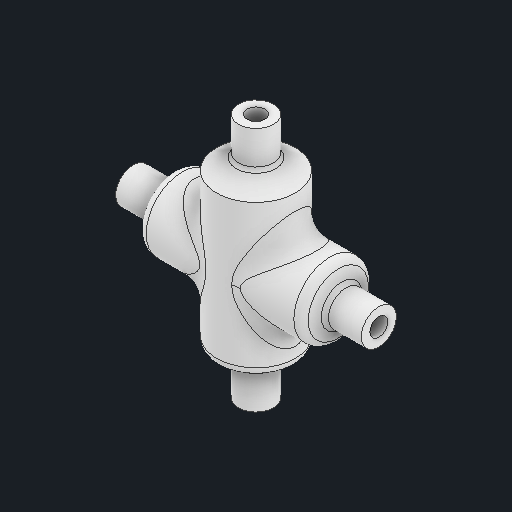
# Autodesk Inventor part: C
Saved by Autodesk Inventor 2026.2 (Build 302298010, 298A)
## iProperties
Created: 2026-03-19
Part Number: C
Material: PC/ABS 플라스틱
Document SubType Name: Modeling
Designer: work
Density: 1.1 g/cm^3
Appearance: 매끄러움 - 흰색
Mass: 15.833 g
Surface Area: 45.1342 cm^2
Volume: 14.3936 cm^3
Author: work
Autodesk Inventor part; units mm, degrees
ref_plane "YZ Plane" through (0, 0, 0) normal (1, 0, 0) x (0, 1, 0)
ref_plane "XZ Plane" through (0, 0, 0) normal (0, 1, 0) x (-1, 0, 0)
ref_plane "XY Plane" through (0, 0, 0) normal (0, 0, 1) x (1, 0, 0)
sketch "스케치1" plane through (0, 0, 0) normal (0, 0, 1) x (1, 0, 0)
  line L0 (0, 0) -> (0, 20.3) construction
  line L1 (-19.3, 0) -> (19.3, 0)
  line L2 (-7.5, 20.3) -> (7.5, 20.3)
  line L3 (-19.3, 0) -> (-19.3, 8)
  line L4 (-19.3, 8) -> (0, 8)
  line L5 (-19.3, 3.9) -> (-27.3, 3.9)
  line L6 (-27.3, 3.9) -> (-27.3, 2)
  line L7 (-27.3, 2) -> (-19.3, 2)
  line L8 (19.3, 0) -> (19.3, 8)
  line L9 (19.3, 8) -> (0, 8)
  line L10 (19.3, 3.9) -> (27.3, 3.9)
  line L11 (27.3, 3.9) -> (27.3, 2)
  line L12 (27.3, 2) -> (19.3, 2)
  line L13 (-19.3, 3.9) -> (-17.8077, 8)
  line L14 (19.3, 3.9) -> (17.8077, 8)
  dimension "d0" = 20.3
  dimension "d1" = 38.6
  dimension "d2" = 15
  dimension "d3" = 4
  dimension "d4" = 7.8
  dimension "d5" = 8
  dimension "d6" = 16
  dimension "d8" = 110
  constraints: 30 end point, 6 point on line, 6 symmetric about line, 3 horizontal, 3 perpendicular, 2 midpoint, 2 vertical
  measures "d0" distance of L0.start L0.end
  measures "d1" distance of L1.start L1.end
  measures "d2" distance of L2.start L2.end
  measures "d3" diameter of L7 L1
  measures "d4" diameter of L5 L1
  measures "d5" distance between parallel lines of L3 L6
  measures "d6" diameter of L4 L1
  measures "d8" angle of L5 L13
revolve "회전1" add sketch "스케치1" angle 360 about axis through (-19.3, 0, 0) along (1, 0, 0) contours L3 L13 L4 L9 L14 L8 L1 | L7 L6 L5 L3 | L8 L10 L11 L12
fillet "모깎기1" radius 1 2 edges at (-19.3, -3.9, 0) (19.3, -3.9, 0)
sketch "스케치2" plane through (0, 0, 0) normal (0, 0, 1) x (1, 0, 0)
  line L0 (0, 0) -> (0, -19.3)
  line L1 (0, -19.3) -> (8.75, -19.3)
  line L2 (8.75, -19.3) -> (8.75, 0)
  line L3 (8.75, 0) -> (0, 0)
  line L4 (2, -19.3) -> (2, -27.3)
  line L5 (2, -27.3) -> (3.9, -27.3)
  line L6 (3.9, -27.3) -> (3.9, -19.3)
  line L7 (3.9, -19.3) -> (8.75, -16.4999)
  dimension "d10" = 19.3
  dimension "d11" = 8
  dimension "d12" = 4
  dimension "d13" = 7.8
  dimension "d14" = 17.5
  dimension "d15" = 30
  constraints: 16 end point, 3 perpendicular, 3 point on line, 3 vertical, 1 horizontal
  measures "d10" distance of L0.start L0.end
  measures "d11" distance of L5.end L6.end
  measures "d12" diameter of L4 L0
  measures "d13" diameter of L6 L0
  measures "d14" diameter of L2 L0
  measures "d15" angle of L1 L7
revolve "회전2" add sketch "스케치2" angle 360 about axis through (0, 0, 0) along (0, -1, 0) contours L3 L2 L7 L1 L0 | L1 L6 L5 L4
fillet "모깎기2" radius 1 1 edges at (-3.9, -19.3, 0)
fillet "모깎기3" radius 2 3 edges at (-8.75, -16.4999, 0) (17.8077, -8, 0) (-17.8077, -8, 0)
mirror "미러1" about plane through (0, 0, 0) normal (0, 1, 0) of "회전2", "모깎기2"
fillet "모깎기4" radius 5 7 edges at (6.2426, 5.1388, -6.1313) (6.2431, 5.1395, 6.1307) (6.2425, -5.1387, -6.1313) (6.2425, -5.1387, 6.1314) (-6.2431, 5.1395, 6.1307) (-6.2426, 5.1388, -6.1313) (-8.75, -8, -0.0205)
